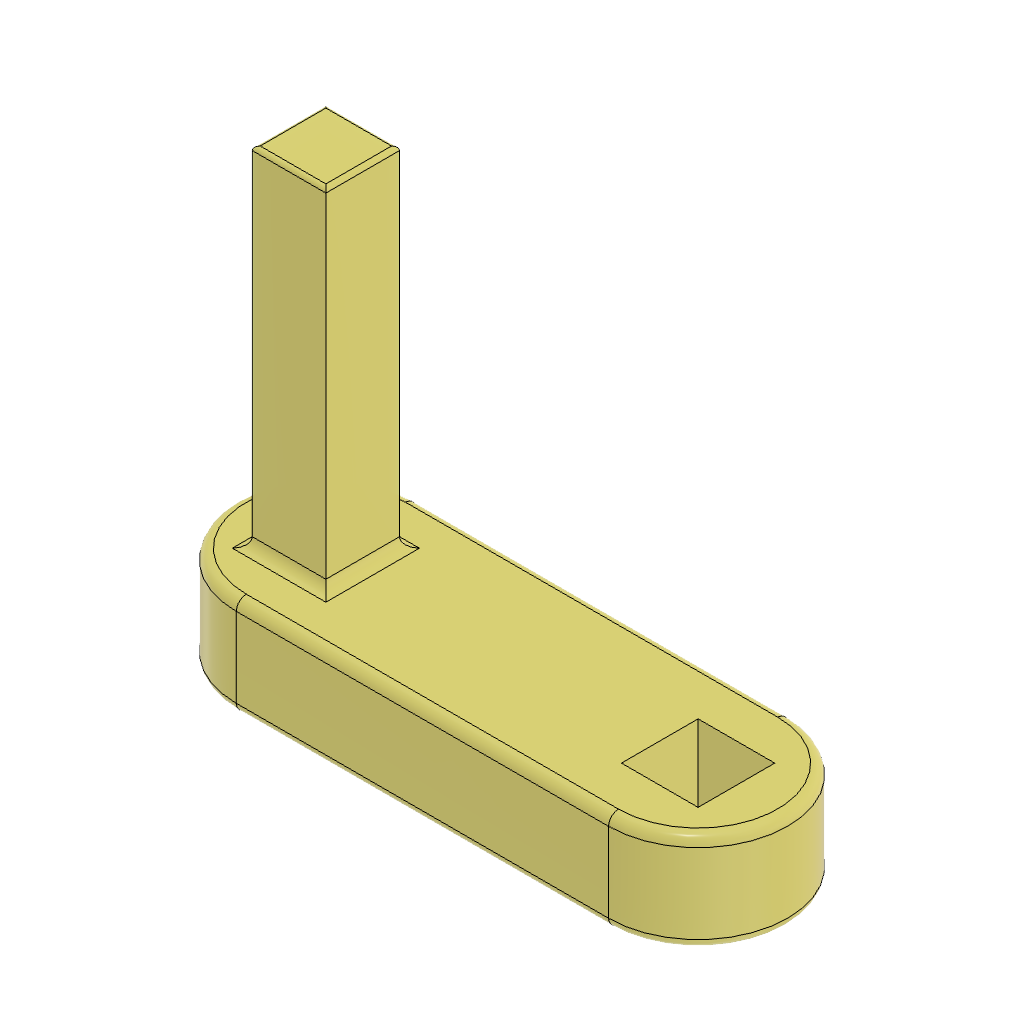
crank_inner (Autodesk Fusion 360 design; units mm, degrees)
part number: 2026-09-20-00-36-53-056
Autodesk Fusion 360 part; units mm, degrees
sketch "Sketch1" plane through (0, 0, 0) normal (0, 0, 1) x (1, 0, 0)
  line L0 (-22.4, -3.7) -> (-15, -3.7)
  line L1 (-15, -3.7) -> (-15, 3.7)
  line L2 (-15, 3.7) -> (-22.4, 3.7)
  line L3 (-22.4, 3.7) -> (-22.4, -3.7)
  line L4 (-22.4, -3.7) -> (-15, 3.7) construction
  line L5 (-15, -3.7) -> (-22.4, 3.7) construction
  line L6 (14.85, -3.85) -> (22.55, -3.85)
  line L7 (22.55, -3.85) -> (22.55, 3.85)
  line L8 (22.55, 3.85) -> (14.85, 3.85)
  line L9 (14.85, 3.85) -> (14.85, -3.85)
  line L10 (14.85, -3.85) -> (22.55, 3.85) construction
  line L11 (22.55, -3.85) -> (14.85, 3.85) construction
  line L12 (0, 1.75) -> (0, 22.5)
  circle A0 centre (-18.7, 0) radius 9
  circle A1 centre (18.7, 0) radius 9
  line L13 (-18.7, -9) -> (18.7, -9)
  line L14 (18.7, -9) -> (18.7, 9)
  line L15 (18.7, 9) -> (-18.7, 9)
  line L16 (-18.7, 9) -> (-18.7, -9)
  line L17 (-18.7, -9) -> (18.7, 9) construction
  line L18 (18.7, -9) -> (-18.7, 9) construction
  line L19 (-3.85, -3.85) -> (3.85, -3.85)
  line L20 (3.85, -3.85) -> (3.85, 3.85)
  line L21 (3.85, 3.85) -> (-3.85, 3.85)
  line L22 (-3.85, 3.85) -> (-3.85, -3.85)
  line L23 (-3.85, -3.85) -> (3.85, 3.85) construction
  line L24 (3.85, -3.85) -> (-3.85, 3.85) construction
  point P0 (-18.7, 0)
  point P1 (18.7, 0)
  dimension "d1" = 7.4
  dimension "d2" = 7.4
  dimension "d3" = 7.7
  dimension "d4" = 7.7
  dimension "d5" = 37.4
  dimension "d7" = 18
  dimension "d8" = 18
  dimension "d9" = 37.4
  dimension "d10" = 18
  dimension "d15" = 7.7
  dimension "d16" = 7.7
  constraint horizontal L0
  constraint perpendicular L0 L1
  constraint parallel L0 L2
  constraint parallel L1 L3
  constraint coincident L4 P0
  constraint coincident L5 P0
  constraint horizontal L6
  constraint perpendicular L6 L7
  constraint parallel L6 L8
  constraint parallel L7 L9
  constraint coincident L10 P1
  constraint coincident L11 P1
  constraint symmetric P0 P1 L12
  constraint coincident P0 A0.centre
  constraint coincident P1 A1.centre
  constraint horizontal L13
  constraint perpendicular L13 L14
  constraint parallel L13 L15
  constraint parallel L14 L16
  constraint coincident L17 origin
  constraint coincident L18 origin
  constraint collinear origin A0.centre P1
  constraint horizontal L19
  constraint perpendicular L19 L20
  constraint parallel L19 L21
  constraint parallel L20 L22
  constraint coincident L23 origin
  constraint coincident L24 origin
  measures "d1" distance of L1.end L2.end
  measures "d2" distance of L0.end L1.end
  measures "d3" distance of L7.end L8.end
  measures "d4" distance of L6.end L7.end
  measures "d5" distance of P0 P1
  measures "d7" diameter of A0
  measures "d8" diameter of A1
  measures "d9" distance of L14.end L15.end
  measures "d10" distance of L13.end L14.end
  measures "d15" distance of L20.end L21.end
  measures "d16" distance of L19.end L20.end
extrude "Extrude1" add sketch "Sketch1" along normal blind 10 contours L0 L2 L3 A0 L16 | L0 L1 L2 A0 L16 | A0 A1 L13 L15 | L6 L7 L8 A1 L14 | L6 L8 L9 A1 L14
extrude "Extrude2" add sketch "Sketch1" along normal blind 45 contours L0 L2 L3 L16 | L0 L1 L2 L16
sketch "Sketch2" plane through (0, 0, 10) normal (0, 0, 1) x (-1, 0, 0)
  line L0 (22.4, 3.7) -> (22.4, -3.7)
  line L1 (22.4, -3.7) -> (15, -3.7)
  line L2 (15, -3.7) -> (15, 3.7)
  line L3 (15, 3.7) -> (22.4, 3.7)
  line L4 (-14.85, 3.85) -> (-14.85, -3.85)
  line L5 (-14.85, -3.85) -> (-22.55, -3.85)
  line L6 (-22.55, -3.85) -> (-22.55, 3.85)
  line L7 (-22.55, 3.85) -> (-14.85, 3.85)
  line L8 (3.85, 3.85) -> (3.85, -3.85)
  line L9 (3.85, -3.85) -> (-3.85, -3.85)
  line L10 (-3.85, -3.85) -> (-3.85, 3.85)
  line L11 (-3.85, 3.85) -> (3.85, 3.85)
  line L12 (-18.7, -9) -> (18.7, -9)
  arc A0 (18.7, -9) -> (18.7, 9) centre (18.7, 0) ccw
  line L13 (18.7, 9) -> (-18.7, 9)
  arc A1 (-18.7, 9) -> (-18.7, -9) centre (-18.7, 0) ccw
  line L14 (-3.85, 3.85) -> (3.85, 3.85)
  line L15 (3.85, 3.85) -> (3.85, -3.85)
  line L16 (3.85, -3.85) -> (-3.85, -3.85)
  line L17 (-3.85, -3.85) -> (-3.85, 3.85)
  constraint horizontal L14
  constraint vertical L15
  constraint horizontal L16
  constraint vertical L17
  constraint coincident L8.end L9.start
  constraint coincident L10.end L11.start
extrude "Extrude3" add sketch "Sketch2" against normal blind 2 contours L8 L9 L10 L11 L14 L15 L16 L17
fillet "Fillet1" radius 1 8 edges at (0, 9, 10) (-27.7, 0, 10) (0, -9, 10) (27.7, 0, 10) (0, -9, 0) (27.7, 0, 0) (0, 9, 0) (-27.7, 0, 0)
fillet "Fillet2" radius 0.4 4 edges at (-18.7, 3.7, 45) (-15, 0, 45) (-18.7, -3.7, 45) (-22.4, 0, 45)
fillet "Fillet3" radius 1 4 edges at (-18.7, 3.7, 10) (-22.4, 0, 10) (-18.7, -3.7, 10) (-15, 0, 10)
equation "d13 = 10 mm + 35 mm"
